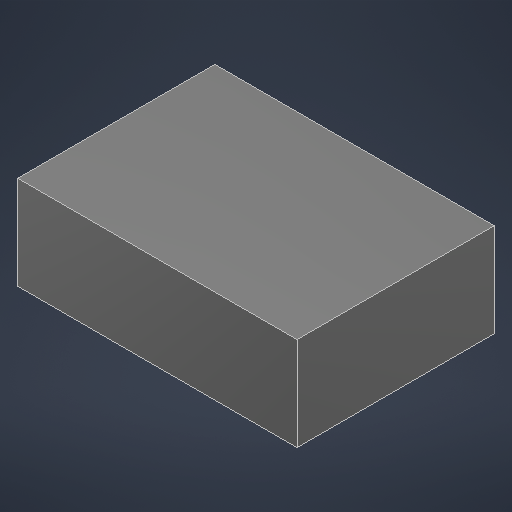
# Autodesk Inventor part: fonte
Saved by Autodesk Inventor 2027.1 (Build 311270010, 270A)
## iProperties
Created: 2026-11-03
Part Number: fonte
Material: Genérico
Document SubType Name: Modeling
Designer: Evellyn
Density: 1 g/cm^3
Appearance: Preto
Author: Evellyn
Autodesk Inventor part; units mm, degrees
ref_plane "YZ Plane" through (0, 0, 0) normal (1, 0, 0) x (0, 1, 0)
ref_plane "XZ Plane" through (0, 0, 0) normal (0, 1, 0) x (-1, 0, 0)
ref_plane "XY Plane" through (0, 0, 0) normal (0, 0, 1) x (1, 0, 0)
sketch "Esboço1" plane through (0, 0, 0) normal (0, 1, 0) x (-1, 0, 0)
  line L0 (-55.25, -39) -> (55.25, -39)
  line L1 (55.25, -39) -> (55.25, 39)
  line L2 (55.25, 39) -> (-55.25, 39)
  line L3 (-55.25, 39) -> (-55.25, -39)
  line L4 (-55.25, -39) -> (55.25, 39) construction
  line L5 (55.25, -39) -> (-55.25, 39) construction
  point P0 (0, 0)
  dimension "d0" = 110.5
  dimension "d1" = 78
  constraints: 12 end point, 2 midpoint, 2 parallel, 1 horizontal, 1 perpendicular
  measures "d0" distance of L2.end L1.end
  measures "d1" distance of L1.end L0.end
extrude "Extrusão1" add sketch "Esboço1" along normal blind 37
